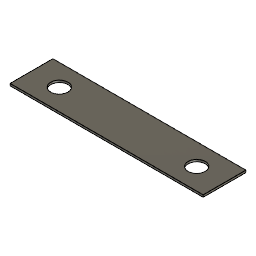
Drill guide 32mm (Autodesk Fusion 360 design; units mm, degrees)
Autodesk Fusion 360 part; units mm, degrees
sketch "Sketch1" plane through (0, 0, 0) normal (0, 0, 1) x (1, 0, 0)
  line L0 (0, 0) -> (45, 0)
  line L1 (45, 0) -> (45, 10)
  line L2 (45, 10) -> (0, 10)
  line L3 (0, 10) -> (0, 0)
  dimension "d1" = 45
  dimension "d2" = 10
  constraint horizontal L0
  constraint vertical L1
  constraint horizontal L2
  constraint vertical L3
  constraint coincident L0.start L3.end
  measures "d1" distance of L0.start L0.end
  measures "d2" distance of L0.start L2.end
extrude "Extrude1" add sketch "Sketch1" along normal blind 0.5
sketch "Sketch2" plane through (0, 0, 0.5) normal (0, 0, 1) x (-1, 0, 0)
  line L0 (0, -10) -> (0, 0)
  line L1 (0, 0) -> (-45, 0)
  line L2 (-45, 0) -> (-45, -10)
  line L3 (-45, -10) -> (0, -10)
  line L4 (0, -10) -> (-22.5, -10)
  line L5 (-22.5, -10) -> (-22.5, 0)
  line L6 (-22.5, -5) -> (-38.5, -5)
  line L7 (-38.5, -5) -> (-6.5, -5)
  circle A0 centre (-6.5, -5) radius 2
  circle A1 centre (-38.5, -5) radius 2
  dimension "d5" = 22.5
  dimension "d6" = 16
  dimension "d7" = 32
  dimension "d8" = 4
  dimension "d9" = 4
  constraint coincident L0.start L3.end
  constraint perpendicular L2 L4
  constraint midpoint L1 L5.end
  constraint midpoint L5 L6.start
  constraint perpendicular L5 L6
  constraint perpendicular L5 L7
  constraint coincident L7.end A0.centre
  constraint coincident L6.end L7.start
  measures "d5" distance of L0.start L4.end
  measures "d6" distance of L6.start L6.end
  measures "d7" distance of L6.end L7.end
  measures "d8" diameter of A0
  measures "d9" diameter of A1
extrude "Extrude2" cut sketch "Sketch2" against normal blind 7654 contours A0 | A1
equation "d5 = ( 45 / 2 ) * 1 mm"
